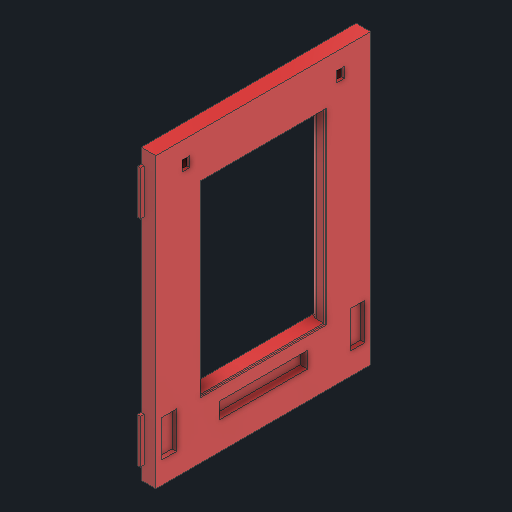
# Autodesk Inventor part: 7_4_1_arriere_base
Saved by Autodesk Inventor 2026 (Build 300175000, 175)
## iProperties
Created: 2025-06-21
Part Number: 7_4_1_arriere_base
Material: Generic
Document SubType Name: Modeling
Designer: remg9
Density: 1 g/cm^3
Appearance: Default
Author: remg9
Autodesk Inventor part; units mm, degrees
ref_plane "YZ Plane" through (0, 0, 0) normal (1, 0, 0) x (0, 1, 0)
ref_plane "XZ Plane" through (0, 0, 0) normal (0, 1, 0) x (-1, 0, 0)
ref_plane "XY Plane" through (0, 0, 0) normal (0, 0, 1) x (1, 0, 0)
sketch "Sketch1" plane through (0, 0, 0) normal (1, 0, 0) x (0, 1, 0)
  line L0 (0, 0) -> (196, 0)
  line L1 (196, 0) -> (196, -146)
  line L2 (196, -146) -> (0, -146)
  line L3 (0, 0) -> (0, -146)
  dimension "d0" = 146
  dimension "d1" = 196
  constraints: 8 end point, 1 horizontal, 1 parallel, 1 perpendicular, 1 vertical
  measures "d0" distance of L0.end L1.end
  measures "d1" distance of L1.end L2.end
extrude "Extrusion1" add sketch "Sketch1" along normal blind 10
sketch "Sketch2" plane through (10, 0, 0) normal (1, 0, 0) x (0, 0, -1)
  line L0 (31, 165) -> (115, 165)
  line L1 (115, 165) -> (115, 39.5)
  line L2 (115, 39.5) -> (31, 39.5)
  line L3 (31, 39.5) -> (31, 165)
  line L4 (30, 166) -> (116, 166)
  line L5 (116, 166) -> (116, 38.5)
  line L6 (116, 38.5) -> (30, 38.5)
  line L7 (30, 38.5) -> (30, 166)
  line L8 (0, 196) -> (0, 0) projected
  line L9 (146, 0) -> (146, 196) projected
  line L10 (146, 196) -> (0, 196) projected
  line L11 (98, 0) -> (146, 0) projected
  line L12 (0, 0) -> (146, 0) projected
  dimension "d7" = 1
  dimension "d8" = 1
  dimension "d9" = 1
  dimension "d10" = 1
  dimension "d11" = 30
  dimension "d12" = 30
  dimension "d13" = 30
  dimension "d42" = 39.5
  constraints: 16 end point, 4 parallel, 2 horizontal, 2 perpendicular
  measures "d7" distance between parallel lines of L5 L1
  measures "d8" distance between parallel lines of L7 L3
  measures "d9" distance between parallel lines of L4 L0
  measures "d10" distance between parallel lines of L6 L2
  measures "d11" distance between parallel lines of L8 L7
  measures "d12" distance between parallel lines of L9 L5
  measures "d13" distance between parallel lines of L10 L4
  measures "d42" distance between parallel lines of L12 L2
extrude "Extrusion2" cut sketch "Sketch2" against normal blind 1 contours L4 L5 L6 L7
sketch "Sketch3" plane through (10, 0, 0) normal (1, 0, 0) x (0, 0, -1)
  line L0 (73, -57.8822) -> (73, 234.4582) construction
  line L1 (0, 196) -> (0, 0) construction
  line L2 (4, 40) -> (14, 40)
  line L3 (14, 40) -> (14, 15)
  line L4 (14, 15) -> (4, 15)
  line L5 (4, 15) -> (4, 40)
  line L6 (0, 0) -> (146, 0) projected
  line L7 (142, 40) -> (132, 40)
  line L8 (132, 40) -> (132, 15)
  line L9 (132, 15) -> (142, 15)
  line L10 (142, 15) -> (142, 40)
  point P0 (48, 0)
  dimension "d17" = 73
  dimension "d18" = 10
  dimension "d19" = 25
  dimension "d20" = 4
  dimension "d21" = 15
  constraints: 18 end point, 5 symmetric about line, 2 parallel, 1 horizontal, 1 perpendicular, 1 vertical
  measures "d17" distance between parallel lines of L1 L0
  measures "d18" distance of L3.end L4.end
  measures "d19" distance of L2.end L3.end
  measures "d20" distance between parallel lines of L1 L5
  measures "d21" distance between parallel lines of L6 L4
extrude "Extrusion3" cut sketch "Sketch3" against normal blind 3
sketch "Sketch4" plane through (10, 0, 0) normal (1, 0, 0) x (0, 0, -1)
  line L0 (43, 30) -> (103, 30)
  line L1 (103, 30) -> (103, 19)
  line L2 (103, 19) -> (43, 19)
  line L3 (43, 19) -> (43, 30)
  line L4 (0, 196) -> (0, 0) projected
  line L5 (0, 0) -> (146, 0) projected
  point P0 (73, 19)
  dimension "d24" = 73
  dimension "d25" = 60
  dimension "d26" = 11
  dimension "d41" = 19
  constraints: 8 end point, 2 parallel, 1 horizontal, 1 midpoint, 1 perpendicular
  measures "d24" distance from line of L4 point (73, 19)
  measures "d25" distance of L1.end L2.end
  measures "d26" distance between parallel lines of L2 L0
  measures "d41" distance between parallel lines of L5 L2
extrude "Extrusion4" cut sketch "Sketch4" against normal blind 5
sketch "Sketch5" plane through (10, 0, 0) normal (1, 0, 0) x (0, 0, -1)
  line L0 (31, 165) -> (115, 165)
  line L1 (115, 165) -> (115, 39.5)
  line L2 (115, 39.5) -> (31, 39.5)
  line L3 (31, 39.5) -> (31, 165)
  line L4 (115, 39.5) -> (115, 165) projected
  line L5 (115, 165) -> (31, 165) projected
  line L6 (31, 165) -> (31, 39.5) projected
  line L7 (31, 39.5) -> (115, 39.5) projected
  point P0 (0, 0)
  constraints: 8 end point, 4 collinear, 2 parallel, 1 horizontal, 1 perpendicular
extrude "Extrusion5" cut sketch "Sketch5" against normal through all
sketch "Sketch6" plane through (10, 0, 0) normal (1, 0, 0) x (0, 0, -1)
  line L0 (18, 184.5) -> (23, 184.5)
  line L1 (23, 184.5) -> (23, 177.5)
  line L2 (23, 177.5) -> (18, 177.5)
  line L3 (18, 177.5) -> (18, 184.5)
  line L4 (123, 177.5) -> (128, 177.5)
  line L5 (128, 177.5) -> (128, 184.5)
  line L6 (128, 184.5) -> (123, 184.5)
  line L7 (123, 184.5) -> (123, 177.5)
  line L8 (23, 181) -> (123, 181) construction
  line L9 (146, 196) -> (0, 196) construction
  line L10 (73, 184.5) -> (73, 171.1775) construction
  point P0 (0, 0)
  point P1 (73, 196)
  point P2 (73, 181)
  dimension "d31" = 5
  dimension "d32" = 7
  dimension "d33" = 15
  dimension "d34" = 100
  constraints: 20 end point, 4 midpoint, 4 parallel, 3 horizontal, 2 collinear, 2 perpendicular, 2 point on line, 1 vertical
  measures "d31" distance of L4.start L4.end
  measures "d32" distance of L4.end L5.end
  measures "d33" distance between parallel lines of L9 L8
  measures "d34" distance of L8.start L8.end
extrude "Extrusion6" cut sketch "Sketch6" against normal through all
sketch "Sketch7" plane through (0, 0, 0) normal (-1, 0, 0) x (0, 0, 1)
  line L0 (-139, 186.5) -> (-7, 186.5)
  line L1 (-7, 186.5) -> (-7, 175.5)
  line L2 (-7, 175.5) -> (-139, 175.5)
  line L3 (-139, 175.5) -> (-139, 186.5)
  line L4 (-123, 181) -> (-23, 181) construction
  line L5 (-73, 187.2077) -> (-73, 176.3972) construction
  line L6 (-23, 177.5) -> (-23, 184.5) construction
  line L7 (-123, 184.5) -> (-123, 177.5) construction
  line L8 (-18, 184.5) -> (-18, 177.5) construction
  point P0 (0, 0)
  point P1 (-73, 181)
  point P2 (-7, 181)
  point P3 (-73, 186.5)
  dimension "d37" = 11
  dimension "d38" = 11
  constraints: 12 end point, 5 midpoint, 3 point on line, 2 horizontal, 2 parallel, 1 perpendicular, 1 vertical
  measures "d37" distance of L0.end L1.end
  measures "d38" distance between parallel lines of L1 L8
extrude "Extrusion7" cut sketch "Sketch7" against normal blind 8
sketch "Sketch8" plane through (0, 0, -146) normal (0, 0, -1) x (-1, 0, 0)
  line L0 (-2, 186) -> (0, 186)
  line L1 (0, 186) -> (0, 156)
  line L2 (0, 156) -> (-2, 156)
  line L3 (-2, 156) -> (-2, 186)
  line L4 (-2, 40) -> (0, 40)
  line L5 (0, 40) -> (0, 10)
  line L6 (0, 10) -> (-2, 10)
  line L7 (-2, 10) -> (-2, 40)
  line L8 (0, 0) -> (0, 196) projected
  line L9 (0, 196) -> (-10, 196) projected
  line L10 (0, 0) -> (-10, 0) projected
  dimension "d43" = 30
  dimension "d44" = 2
  dimension "d45" = 10
  dimension "d46" = 10
  constraints: 16 end point, 4 parallel, 2 collinear, 2 horizontal, 2 perpendicular, 2 point on line
  measures "d43" distance of L0.end L1.end
  measures "d44" distance of L0.start L0.end
  measures "d45" distance between parallel lines of L9 L0
  measures "d46" distance between parallel lines of L10 L6
extrude "Extrusion8" add sketch "Sketch8" along normal blind 2.5
sketch "Sketch9" plane through (0, 0, 0) normal (0, 0, 1) x (1, 0, 0)
  line L0 (0, 186) -> (2, 186)
  line L1 (2, 186) -> (2, 156)
  line L2 (2, 156) -> (0, 156)
  line L3 (0, 156) -> (0, 186)
  line L4 (0, 40) -> (2, 40)
  line L5 (2, 40) -> (2, 10)
  line L6 (2, 10) -> (0, 10)
  line L7 (0, 10) -> (0, 40)
  line L8 (0, 196) -> (10, 196) projected
  line L9 (0, 0) -> (10, 0) projected
  line L10 (0, 196) -> (0, 0) projected
  dimension "d49" = 2
  dimension "d50" = 30
  dimension "d51" = 10
  dimension "d52" = 10
  constraints: 16 end point, 4 parallel, 2 collinear, 2 horizontal, 2 perpendicular, 2 point on line
  measures "d49" distance of L0.start L0.end
  measures "d50" distance of L2.end L0.start
  measures "d51" distance between parallel lines of L8 L0
  measures "d52" distance between parallel lines of L9 L6
extrude "Extrusion9" add sketch "Sketch9" along normal blind 2.5
fillet "Fillet1" radius 4 3 edges at (0, 102.25, -31) (0, 102.25, -115) (0, 165, -73)
body "Solid1"
